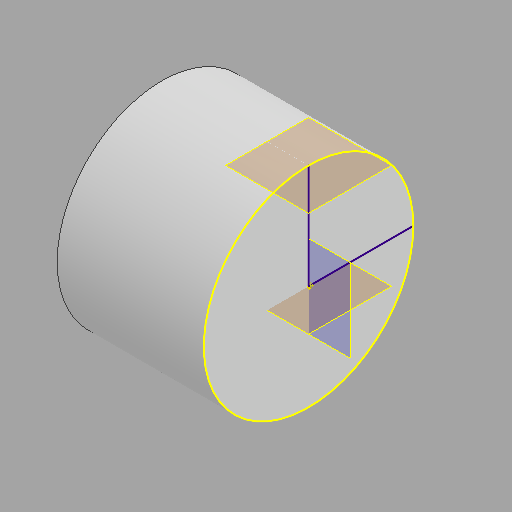
# Autodesk Inventor part: Motor
Saved by Autodesk Inventor 2027.1 (Build 311270010, 270A)
## iProperties
Created: 2026-10-23
Part Number: Motor
Material: Generic
Document SubType Name: Modeling
Designer: PWYNNE
Density: 1 g/cm^3
Appearance: Default
Author: PWYNNE
Autodesk Inventor part; units mm, degrees
ref_plane "YZ Plane" through (0, 0, 0) normal (1, 0, 0) x (0, 1, 0)
ref_plane "XZ Plane" through (0, 0, 0) normal (0, 1, 0) x (-1, 0, 0)
ref_plane "XY Plane" through (0, 0, 0) normal (0, 0, 1) x (1, 0, 0)
sketch "Sketch1" plane through (0, 0, 0) normal (1, 0, 0) x (0, 1, 0)
  circle A0 centre (0, 0) radius 27.8
  dimension "d0" = 55.6
  constraints: 1 centre point, 1 coincident
  measures "d0" diameter of A0
extrude "Extrusion1" add sketch "Sketch1" along normal blind 38.9
sketch "Sketch2" plane through (38.9, 0, 0) normal (1, 0, 0) x (0, 0, -1)
  circle A0 centre (0, 0) radius 27.8 projected
  line L0 (0, 0) -> (0, 27.8)
  line L1 (0, 0) -> (27.8, 0)
  constraints: 4 end point, 2 point on circle, 1 perpendicular, 1 vertical
ref_plane "Work Plane1" through (38.9, 27.8, 0) normal (0, 1, 0) x (-1, 0, 0)
ref_plane "Work Plane2" through (38.9, 0, 0) normal (0, 1, 0) x (-1, 0, 0)
ref_plane "Work Plane3" through (38.9, 0, 0) normal (0, 0, -1) x (-1, 0, 0)
body "Solid1"
